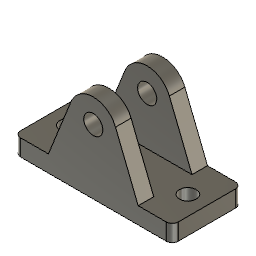
base (Autodesk Fusion 360 design; units mm, degrees)
part number: 2026-08-13-13-51-28-475
Autodesk Fusion 360 part; units mm, degrees
sketch "Sketch1" plane through (0, 0, 0) normal (0, 0, 1) x (1, 0, 0)
  line L0 (66, 29) -> (-66, 29)
  line L1 (-66, 29) -> (-66, -29)
  line L2 (-66, -29) -> (66, -29)
  line L3 (66, -29) -> (66, 29)
  line L4 (66, 29) -> (-66, -29) construction
  line L5 (-66, 29) -> (66, -29) construction
  circle A0 centre (-50, 0) radius 7
  circle A1 centre (50, 0) radius 7
  dimension "d1" = 132
  dimension "d2" = 58
  dimension "d3" = 14
  dimension "d4" = 14
  dimension "d5" = 16
  dimension "d6" = 16
  constraint horizontal L0
  constraint perpendicular L0 L1
  constraint parallel L0 L2
  constraint parallel L1 L3
  constraint coincident L4 origin
  constraint coincident L5 origin
  measures "d1" distance of L1.end L2.end
  measures "d2" distance of L0.end L1.end
  measures "d3" diameter of A0
  measures "d4" diameter of A1
  measures "d5" distance of L1 A0.centre
  measures "d6" distance of L3 A1.centre
extrude "Extrude1" add sketch "Sketch1" along normal blind 14
sketch "Sketch2" plane through (0, -29, 0) normal (0, -1, 0) x (1, 0, 0)
  line L0 (-66, 0) -> (66, 0)
  line L1 (66, 0) -> (66, 14)
  line L2 (66, 14) -> (-66, 14)
  line L3 (-66, 14) -> (-66, 0)
  line L4 (0, 14) -> (37.5, 14)
  line L5 (0, 14) -> (-37.5, 14)
  line L6 (0, 46) -> (0, 54)
  circle A0 centre (0, 54) radius 8
  line L7 (-18.575, 61.4141) -> (-37.5, 14)
  line L8 (37.5, 14) -> (18.575, 61.4141)
  arc A1 (18.575, 61.4141) -> (-18.575, 61.4141) centre (0, 54) ccw
  dimension "d9" = 37.5
  dimension "d10" = 37.5
  dimension "d11" = 40
  dimension "d12" = 16
  dimension "d13" = 40
  constraint midpoint L2 L4.start
  constraint parallel L2 L4
  constraint parallel L2 L5
  constraint perpendicular L2 L6
  constraint coincident L6.end A0.centre
  constraint concentric A0 A1
  constraint tangent L7 A1
  constraint tangent L8 A1
  constraint coincident A0 L6.start
  measures "d9" distance of L4.start L4.end
  measures "d10" distance of L4.start L5.end
  measures "d11" distance of L4.start L6.end
  measures "d12" diameter of A0
  measures "d13" diameter of A1
extrude "Extrude2" add sketch "Sketch2" against normal blind 58 contours L2 L4 L5 L7 L8 A1
sketch "Sketch3" plane through (0, 0, 0) normal (0, 0, -1) x (1, 0, 0)
  circle A0 centre (50, 0) radius 7
  circle A1 centre (-50, 0) radius 7
  line L0 (66, -29) -> (66, 29)
  line L1 (66, 29) -> (-66, 29)
  line L2 (-66, 29) -> (-66, -29)
  line L3 (-66, -29) -> (66, -29)
  line L4 (-37.5, 16) -> (37.5, 16)
  line L5 (37.5, 16) -> (37.5, -16)
  line L6 (37.5, -16) -> (-37.5, -16)
  line L7 (-37.5, -16) -> (-37.5, 16)
  line L8 (-37.5, 16) -> (37.5, -16) construction
  line L9 (37.5, 16) -> (-37.5, -16) construction
  dimension "d16" = 75
  dimension "d17" = 32
  constraint horizontal L4
  constraint perpendicular L4 L5
  constraint parallel L4 L6
  constraint parallel L5 L7
  constraint coincident L8 origin
  constraint coincident L9 origin
  measures "d16" distance of L5.end L6.end
  measures "d17" distance of L4.end L5.end
sketch "Sketch4" plane through (37.1668, 0, 14.8348) normal (0.928751, 0, 0.370704) x (0, 1, 0)
  line L0 (-29, 50.1526) -> (-29, -0.8989)
  line L1 (-29, -0.8989) -> (29, -0.8989)
  line L2 (29, -0.8989) -> (29, 50.1526)
  line L3 (29, 50.1526) -> (-29, 50.1526)
extrude "Extrude3" cut sketch "Sketch3" against normal blind 100 contours L4 L5 L6 L7
extrude "Extrude4" add 1 faces at (37.5, -5.3333, 9.3333) along direction (-1, 0, 0) blind 75
fillet "Fillet1" radius 5 1 edges at (66, 29, 7)
fillet "Fillet2" radius 5 1 edges at (66, -29, 7)
fillet "Fillet3" radius 5 1 edges at (-66, -29, 7)
fillet "Fillet4" radius 5 1 edges at (-66, 29, 7)
